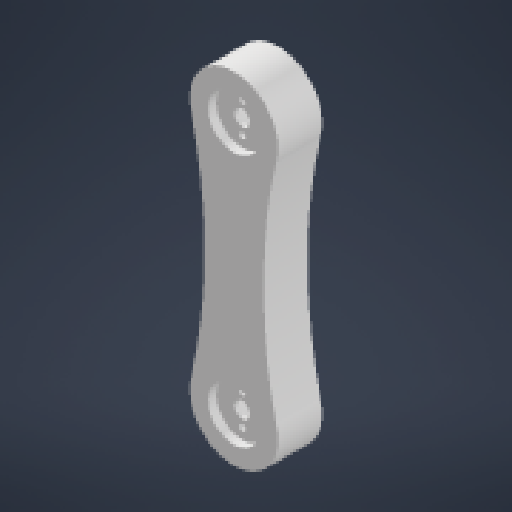
# Autodesk Inventor part: thanh nối
Saved by Autodesk Inventor 2026.2 (Build 302298000, 298)
## iProperties
Created: 2025-11-18
Part Number: thanh nối
Material: Generic
Document SubType Name: Modeling
Designer: thita
Density: 1 g/cm^3
Appearance: Default
Author: thita
Autodesk Inventor part; units mm, degrees
ref_plane "YZ Plane" through (0, 0, 0) normal (1, 0, 0) x (0, 1, 0)
ref_plane "XZ Plane" through (0, 0, 0) normal (0, 1, 0) x (-1, 0, 0)
ref_plane "XY Plane" through (0, 0, 0) normal (0, 0, 1) x (1, 0, 0)
sketch "Sketch1" plane through (0, 0, 0) normal (0, 0, 1) x (1, 0, 0)
  arc A0 (-20, 6.4031) -> (20, 6.4031) centre (0, 0) ccw
  arc A1 (20, 113.5969) -> (-20, 113.5969) centre (0, 120) ccw
  arc A2 (20, 113.5969) -> (20, 6.4031) centre (256.3854, 60) ccw
  arc A3 (-20, 6.4031) -> (-20, 113.5969) centre (-256.3854, 60) ccw
  dimension "d1" = 42
  dimension "d2" = 42
  constraints: 8 point on circle, 4 centre point, 1 coincident
  measures "d1" diameter of A0
  measures "d2" diameter of A1
extrude "Extrusion1" add sketch "Sketch1" along normal blind 21
sketch "Sketch2" plane through (0, 0, 21) normal (0, 0, 1) x (1, 0, 0)
  circle A0 centre (0, 0) radius 18
  arc A1 (20, 113.5969) -> (-20, 113.5969) centre (0, 120) ccw projected
  circle A2 centre (0, 120) radius 18
  dimension "d7" = 36
  dimension "d9" = 36
  constraints: 2 centre point, 2 coincident
  measures "d7" diameter of A0
  measures "d9" diameter of A2
extrude "Extrusion2" cut sketch "Sketch2" against normal blind 15
sketch "Sketch3" plane through (0, 0, 0) normal (0, 0, -1) x (-1, 0, 0)
  circle A0 centre (0, 0) radius 12.25
  circle A1 centre (0, 120) radius 18 projected
  circle A2 centre (0, 120) radius 12.25
  dimension "d12" = 24.5
  dimension "d13" = 24.5
  constraints: 2 centre point, 2 coincident
  measures "d12" diameter of A0
  measures "d13" diameter of A2
extrude "Extrusion3" cut sketch "Sketch3" against normal blind 4 contours A0 | A2
sketch "Sketch4" plane through (0, 0, 4) normal (0, 0, -1) x (-1, 0, 0)
  circle A0 centre (0, 0) radius 3.75
  circle A1 centre (0, 120) radius 12.25 projected
  circle A2 centre (0, 120) radius 3.75
  circle A3 centre (0, -7.25) radius 1.5
  circle A4 centre (0, 7.25) radius 1.5
  circle A5 centre (0, 112.75) radius 1.5
  circle A6 centre (0, 127.25) radius 1.5
  dimension "d17" = 7.5
  dimension "d20" = 3
  dimension "d21" = 3
  dimension "d22" = 3
  dimension "d23" = 3
  constraints: 6 centre point, 1 coincident
  measures "d17" diameter of A2
  measures "d20" diameter of A3
  measures "d21" diameter of A4
  measures "d22" diameter of A5
  measures "d23" diameter of A6
extrude "Extrusion4" cut sketch "Sketch4" against normal through all contours A0 | A2 | A3 | A4 | A5 | A6
mirror "Mirror1" about plane through (0, 60, 0) normal (0, 0, -1) remove original yes
body "Solid1"
